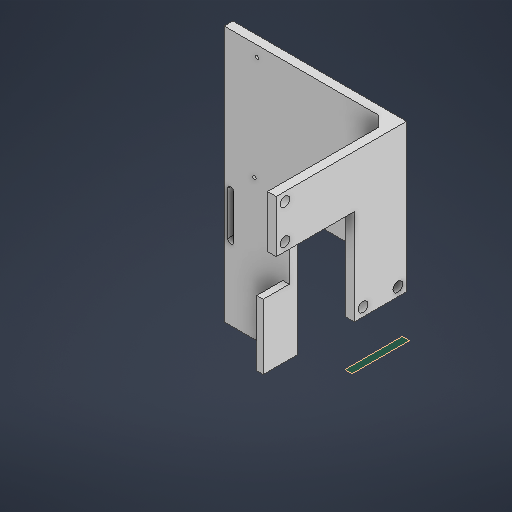
# Autodesk Inventor part: 01_4_3_support_electronique
Saved by Autodesk Inventor 2026 (Build 300175000, 175)
## iProperties
Created: 2025-06-19
Part Number: 01_4_3_support_electronique
Material: Générique
Document SubType Name: Modeling
Designer: virgi
Density: 1 g/cm^3
Appearance: Par défaut
Author: virgi
Autodesk Inventor part; units mm, degrees
ref_plane "YZ Plane" through (0, 0, 0) normal (1, 0, 0) x (0, 1, 0)
ref_plane "XZ Plane" through (0, 0, 0) normal (0, 1, 0) x (-1, 0, 0)
ref_plane "XY Plane" through (0, 0, 0) normal (0, 0, 1) x (1, 0, 0)
sketch "Esquisse1" plane through (0, 0, 0) normal (0, 1, 0) x (-1, 0, 0)
  line L0 (-0.0088, 21.0012) -> (-0.0088, -2.9988)
  line L1 (-0.0088, -2.9988) -> (79.9912, -2.9988)
  line L2 (79.9912, -2.9988) -> (79.9912, 1.0012)
  line L3 (79.9912, 1.0012) -> (3.9912, 1.0012)
  line L4 (-0.0088, 21.0012) -> (3.9912, 21.0012)
  line L5 (3.9912, 21.0012) -> (3.9912, 1.0012)
  line L6 (67.3314, 1.0012) -> (-38.8153, 1.0012) construction
  dimension "d4" = 4
  dimension "d5" = 80
  dimension "d17" = 20
  dimension "d42" = 4
  constraints: 14 end point, 4 perpendicular, 2 horizontal, 1 point on line, 1 vertical
  measures "d4" distance between parallel lines of L3 L1
  measures "d5" distance between parallel lines of L0 L2
  measures "d17" distance between parallel lines of L4 L3
  measures "d42" distance between parallel lines of L0 L5
extrude "Extrusion1" add sketch "Esquisse1" along normal blind 68
sketch "Esquisse2" plane through (-3.9912, 0, 1.0012) normal (-1, 0, 0) x (0, 0, 1)
  line L0 (18.5952, 4) -> (-12.3753, 4) construction
  line L1 (0, 68) -> (20, 68) construction
  line L2 (20, 0) -> (20, 68) projected
  point P0 (-1.0012, 0)
  point P1 (16, 4)
  point P2 (0, 4)
  dimension "d15" = 64
  dimension "d16" = 16
  dimension "d18" = 4
  constraints: 2 end point, 2 point on line, 1 horizontal
  measures "d15" distance between parallel lines of L0 L1
  measures "d16" distance of point (0, 4) point (16, 4)
  measures "d18" distance from line of point (16, 4) L2
hole "Perçage1" at (-3.9912, 4, 17.0012) at (-3.9912, 4, 1.0012) direction (1, 0, 0) diameter 4.5 end through all
sketch "Esquisse3" plane through (-79.9912, 0, 1.0012) normal (0, 0, 1) x (1, 0, 0)
  line L0 (0, 0) -> (0, 68) projected
  line L1 (0, 68) -> (76, 68) projected
  line L2 (0, 0) -> (76, 0) projected
  point P0 (79.9912, 0)
  point P1 (15.174, 63)
  point P2 (13.952, 14.527)
  point P3 (66.038, 46.831)
  point P4 (66.038, 19.431)
  dimension "d26" = 15.174
  dimension "d27" = 5
  dimension "d28" = 13.952
  dimension "d30" = 48.473
  dimension "d31" = 21.169
  dimension "d32" = 50.864
  dimension "d34" = 27.4
  dimension "d35" = 0
  measures "d26" distance from line of L0 point (15.174, 63)
  measures "d27" distance from line of L1 point (15.174, 63)
  measures "d28" distance from line of L0 point (13.952, 14.527)
  measures "d30" vertical distance of point (13.952, 14.527) point (15.174, 63)
  measures "d31" distance from line of point (66.038, 46.831) L1
  measures "d32" horizontal distance of point (66.038, 46.831) point (15.174, 63)
  measures "d34" distance of point (66.038, 46.831) point (66.038, 19.431)
  measures "d35" horizontal distance of point (66.038, 46.831) point (66.038, 19.431)
hole "Perçage2" at (-64.8172, 63, 1.0012) at (-66.0392, 14.527, 1.0012) at (-13.9532, 46.831, 1.0012) at (-13.9532, 19.431, 1.0012) direction (0, 0, -1) diameter 1.6 end through all
sketch "Esquisse4" plane through (-79.9912, 0, 1.0012) normal (0, 0, 1) x (1, 0, 0)
  line L0 (0, 0) -> (76, 0)
  line L1 (76, 0) -> (76, 10)
  line L2 (76, 10) -> (0, 10)
  line L3 (0, 10) -> (0, 0)
  point P0 (79.9912, 0)
  point P1 (0, 0)
  dimension "d36" = 10
  constraints: 8 end point, 3 point on line, 2 parallel, 1 horizontal, 1 perpendicular
  measures "d36" distance between parallel lines of L0 L2
extrude "Extrusion2" cut sketch "Esquisse4" against normal blind 68
chamfer "Chanfrein1" distance 5 angle 45 1 edges at (-3.9912, 39, 1.0012)
ref_plane "Plan de construction2" through (0, -20, 0) normal (0, -1, 0) x (1, 0, 0)
sketch "Esquisse5" plane through (-3.9912, 0, 21.0012) normal (-1, 0, 0) x (0, 0, 1)
  line L0 (0, 68) -> (36, 68)
  line L1 (36, 68) -> (36, 44)
  line L2 (36, 44) -> (0, 44)
  line L3 (0, 44) -> (0, 68)
  line L4 (-24, 10) -> (-24, 68) projected
  point P0 (-21.0012, 0)
  dimension "d44" = 60
  dimension "d45" = 24
  constraints: 8 end point, 2 parallel, 1 coincident, 1 horizontal, 1 perpendicular
  measures "d44" distance between parallel lines of L4 L1
  measures "d45" distance between parallel lines of L2 L0
extrude "Extrusion3" add sketch "Esquisse5" against normal blind 4
sketch "Esquisse6" plane through (-3.9912, 0, -2.9988) normal (-1, 0, 0) x (0, 0, 1)
  line L0 (24, 44) -> (60, 44) projected
  line L1 (60, 44) -> (60, 68) projected
  line L2 (9, 68) -> (60, 68) projected
  point P0 (2.9988, 0)
  point P1 (56, 48)
  point P2 (56, 64)
  dimension "d55" = 4
  dimension "d56" = 4
  dimension "d57" = 4
  dimension "d58" = 4
  measures "d55" distance from line of L0 point (56, 48)
  measures "d56" distance from line of L1 point (56, 48)
  measures "d57" distance from line of L1 point (56, 64)
  measures "d58" distance from line of L2 point (56, 64)
hole "Perçage3" at (-3.9912, 48, 53.0012) at (-3.9912, 64, 53.0012) direction (1, 0, 0) diameter 4.4 end through all
sketch "Esquisse7" plane through (-79.9912, 10, 1.0012) normal (0, 0, 1) x (1, 0, 0)
  line L0 (0, 0) -> (30, 0)
  line L1 (30, 0) -> (30, -60)
  line L2 (30, -60) -> (0, -60)
  line L3 (0, -60) -> (0, 0)
  line L4 (0, 0) -> (71, 0) projected
  point P0 (79.9912, -10)
  dimension "d60" = 30
  dimension "d61" = 60
  constraints: 8 end point, 2 parallel, 1 horizontal, 1 perpendicular
  measures "d60" distance between parallel lines of L3 L1
  measures "d61" distance between parallel lines of L4 L2
extrude "Extrusion4" add sketch "Esquisse7" against normal blind 4
sketch "Esquisse8" plane through (-79.9912, 68, 1.0012) normal (0, 0, 1) x (1, 0, 0)
  line L0 (30, -118) -> (27, -118)
  line L1 (27, -118) -> (27, -88)
  line L2 (27, -88) -> (30, -88)
  line L3 (30, -88) -> (30, -118)
  line L4 (0, -118) -> (30, -118) projected
  point P0 (79.9912, -68)
  point P1 (28.5, -88)
  dimension "d64" = 3
  dimension "d65" = 30
  constraints: 8 end point, 2 parallel, 1 coincident, 1 horizontal, 1 midpoint, 1 perpendicular
  measures "d64" distance between parallel lines of L3 L1
  measures "d65" distance from line of L4 point (28.5, -88)
extrude "Extrusion5" add sketch "Esquisse8" along normal blind 12
sketch "Esquisse10" plane through (-79.9912, 68, 1.0012) normal (0, 0, 1) x (1, 0, 0)
  line L0 (3, -84) -> (3, -64) construction
  line L1 (4.4, -84) -> (4.4, -64)
  line L2 (1.6, -64) -> (1.6, -84)
  arc A0 (1.6, -84) -> (4.4, -84) centre (3, -84) ccw
  arc A1 (4.4, -64) -> (1.6, -64) centre (3, -64) ccw
  line L3 (0, -118) -> (0, 0) projected
  line L4 (30, -58) -> (71, -58) projected
  point P0 (79.9912, -68)
  point P1 (3, -74)
  dimension "d79" = 3
  dimension "d80" = 20
  dimension "d81" = 6
  dimension "d85" = 2.8
  constraints: 8 end point, 4 point on circle, 4 tangent, 2 centre point, 1 midpoint, 1 parallel, 1 vertical
  measures "d79" distance between parallel lines of L3 L0
  measures "d80" distance of L0.start L0.end
  measures "d81" distance from line of L4 L0.end
  measures "d85" distance between parallel lines of L1 L2
extrude "Extrusion6" cut sketch "Esquisse10" against normal blind 12
